Autodesk Fusion 360 part; units mm, degrees
(part 6 of 9)
equation "d71 = ( ( keyRowOne ) - upperSwitchOpening / 2 ) + faceOriginV"
equation "d72 = ( ( ( layoutGap + keycapSize / 2 + 0 * keyPitch ) - upperSwitchOpening / 2 ) + ( upperSwitchOpening ) ) - ( ( layoutGap + keycapSize / 2 + 0 * keyPitch ) - upperSwitchOpening / 2 )"
equation "d73 = ( ( ( ( keyRowOne ) - upperSwitchOpening / 2 ) + faceOriginV ) + ( upperSwitchOpening ) ) - ( ( ( keyRowOne ) - upperSwitchOpening / 2 ) + faceOriginV )"
equation "d74 = -( shellWall + 1 mm )"
equation "d76 = ( layoutGap + keycapSize / 2 + 1 * keyPitch ) - switchOpening / 2"
equation "d77 = ( ( keyRowOne ) - switchOpening / 2 ) + faceOriginV"
equation "d78 = ( ( ( layoutGap + keycapSize / 2 + 1 * keyPitch ) - switchOpening / 2 ) + ( switchOpening ) ) - ( ( layoutGap + keycapSize / 2 + 1 * keyPitch ) - switchOpening / 2 )"
equation "d79 = ( ( ( ( keyRowOne ) - switchOpening / 2 ) + faceOriginV ) + ( switchOpening ) ) - ( ( ( keyRowOne ) - switchOpening / 2 ) + faceOriginV )"
equation "d80 = -( carrierThickness + 1 mm )"
equation "d82 = ( layoutGap + keycapSize / 2 + 1 * keyPitch ) - upperSwitchOpening / 2"
equation "d83 = ( ( keyRowOne ) - upperSwitchOpening / 2 ) + faceOriginV"
equation "d84 = ( ( ( layoutGap + keycapSize / 2 + 1 * keyPitch ) - upperSwitchOpening / 2 ) + ( upperSwitchOpening ) ) - ( ( layoutGap + keycapSize / 2 + 1 * keyPitch ) - upperSwitchOpening / 2 )"
equation "d85 = ( ( ( ( keyRowOne ) - upperSwitchOpening / 2 ) + faceOriginV ) + ( upperSwitchOpening ) ) - ( ( ( keyRowOne ) - upperSwitchOpening / 2 ) + faceOriginV )"
equation "d86 = -( shellWall + 1 mm )"
equation "d88 = ( layoutGap + keycapSize / 2 + 2 * keyPitch ) - switchOpening / 2"
equation "d89 = ( ( keyRowOne ) - switchOpening / 2 ) + faceOriginV"
equation "d90 = ( ( ( layoutGap + keycapSize / 2 + 2 * keyPitch ) - switchOpening / 2 ) + ( switchOpening ) ) - ( ( layoutGap + keycapSize / 2 + 2 * keyPitch ) - switchOpening / 2 )"
equation "d91 = ( ( ( ( keyRowOne ) - switchOpening / 2 ) + faceOriginV ) + ( switchOpening ) ) - ( ( ( keyRowOne ) - switchOpening / 2 ) + faceOriginV )"
equation "d92 = -( carrierThickness + 1 mm )"
equation "d94 = ( layoutGap + keycapSize / 2 + 2 * keyPitch ) - upperSwitchOpening / 2"
equation "d95 = ( ( keyRowOne ) - upperSwitchOpening / 2 ) + faceOriginV"
equation "d96 = ( ( ( layoutGap + keycapSize / 2 + 2 * keyPitch ) - upperSwitchOpening / 2 ) + ( upperSwitchOpening ) ) - ( ( layoutGap + keycapSize / 2 + 2 * keyPitch ) - upperSwitchOpening / 2 )"
equation "d97 = ( ( ( ( keyRowOne ) - upperSwitchOpening / 2 ) + faceOriginV ) + ( upperSwitchOpening ) ) - ( ( ( keyRowOne ) - upperSwitchOpening / 2 ) + faceOriginV )"
equation "d98 = -( shellWall + 1 mm )"
equation "d100 = ( layoutGap + keycapSize / 2 + 0 * keyPitch ) - switchOpening / 2"
equation "d101 = ( ( keyRowTwo ) - switchOpening / 2 ) + faceOriginV"
equation "d102 = ( ( ( layoutGap + keycapSize / 2 + 0 * keyPitch ) - switchOpening / 2 ) + ( switchOpening ) ) - ( ( layoutGap + keycapSize / 2 + 0 * keyPitch ) - switchOpening / 2 )"
equation "d103 = ( ( ( ( keyRowTwo ) - switchOpening / 2 ) + faceOriginV ) + ( switchOpening ) ) - ( ( ( keyRowTwo ) - switchOpening / 2 ) + faceOriginV )"
equation "d104 = -( carrierThickness + 1 mm )"
equation "d106 = ( layoutGap + keycapSize / 2 + 0 * keyPitch ) - upperSwitchOpening / 2"
equation "d107 = ( ( keyRowTwo ) - upperSwitchOpening / 2 ) + faceOriginV"
equation "d108 = ( ( ( layoutGap + keycapSize / 2 + 0 * keyPitch ) - upperSwitchOpening / 2 ) + ( upperSwitchOpening ) ) - ( ( layoutGap + keycapSize / 2 + 0 * keyPitch ) - upperSwitchOpening / 2 )"
equation "d109 = ( ( ( ( keyRowTwo ) - upperSwitchOpening / 2 ) + faceOriginV ) + ( upperSwitchOpening ) ) - ( ( ( keyRowTwo ) - upperSwitchOpening / 2 ) + faceOriginV )"
equation "d110 = -( shellWall + 1 mm )"
equation "d112 = ( layoutGap + keycapSize / 2 + 1 * keyPitch ) - switchOpening / 2"
equation "d113 = ( ( keyRowTwo ) - switchOpening / 2 ) + faceOriginV"
equation "d114 = ( ( ( layoutGap + keycapSize / 2 + 1 * keyPitch ) - switchOpening / 2 ) + ( switchOpening ) ) - ( ( layoutGap + keycapSize / 2 + 1 * keyPitch ) - switchOpening / 2 )"
equation "d115 = ( ( ( ( keyRowTwo ) - switchOpening / 2 ) + faceOriginV ) + ( switchOpening ) ) - ( ( ( keyRowTwo ) - switchOpening / 2 ) + faceOriginV )"
equation "d116 = -( carrierThickness + 1 mm )"
equation "d118 = ( layoutGap + keycapSize / 2 + 1 * keyPitch ) - upperSwitchOpening / 2"
equation "d119 = ( ( keyRowTwo ) - upperSwitchOpening / 2 ) + faceOriginV"
equation "d120 = ( ( ( layoutGap + keycapSize / 2 + 1 * keyPitch ) - upperSwitchOpening / 2 ) + ( upperSwitchOpening ) ) - ( ( layoutGap + keycapSize / 2 + 1 * keyPitch ) - upperSwitchOpening / 2 )"
equation "d121 = ( ( ( ( keyRowTwo ) - upperSwitchOpening / 2 ) + faceOriginV ) + ( upperSwitchOpening ) ) - ( ( ( keyRowTwo ) - upperSwitchOpening / 2 ) + faceOriginV )"
equation "d122 = -( shellWall + 1 mm )"
equation "d124 = ( layoutGap + keycapSize / 2 + 2 * keyPitch ) - switchOpening / 2"
equation "d125 = ( ( keyRowTwo ) - switchOpening / 2 ) + faceOriginV"
equation "d126 = ( ( ( layoutGap + keycapSize / 2 + 2 * keyPitch ) - switchOpening / 2 ) + ( switchOpening ) ) - ( ( layoutGap + keycapSize / 2 + 2 * keyPitch ) - switchOpening / 2 )"
equation "d127 = ( ( ( ( keyRowTwo ) - switchOpening / 2 ) + faceOriginV ) + ( switchOpening ) ) - ( ( ( keyRowTwo ) - switchOpening / 2 ) + faceOriginV )"
equation "d128 = -( carrierThickness + 1 mm )"
equation "d130 = ( layoutGap + keycapSize / 2 + 2 * keyPitch ) - upperSwitchOpening / 2"
equation "d131 = ( ( keyRowTwo ) - upperSwitchOpening / 2 ) + faceOriginV"
equation "d132 = ( ( ( layoutGap + keycapSize / 2 + 2 * keyPitch ) - upperSwitchOpening / 2 ) + ( upperSwitchOpening ) ) - ( ( layoutGap + keycapSize / 2 + 2 * keyPitch ) - upperSwitchOpening / 2 )"
equation "d133 = ( ( ( ( keyRowTwo ) - upperSwitchOpening / 2 ) + faceOriginV ) + ( upperSwitchOpening ) ) - ( ( ( keyRowTwo ) - upperSwitchOpening / 2 ) + faceOriginV )"
equation "d134 = -( shellWall + 1 mm )"
equation "d136 = ( caseWidth - ledWidth ) / 2"
equation "d137 = ( ledCenter - ledHeight / 2 ) + faceOriginV"
equation "d138 = ( ( ( caseWidth - ledWidth ) / 2 ) + ( ledWidth ) ) - ( ( caseWidth - ledWidth ) / 2 )"
equation "d139 = ( ( ( ledCenter - ledHeight / 2 ) + faceOriginV ) + ( ledHeight ) ) - ( ( ledCenter - ledHeight / 2 ) + faceOriginV )"
equation "d140 = -( shellWall + 1 mm )"
equation "d142 = layoutGap"
equation "d143 = ( controlCenter - displayHeight / 2 ) + faceOriginV"
equation "d144 = ( ( layoutGap ) + ( displayWidth ) ) - ( layoutGap )"
equation "d145 = ( ( ( controlCenter - displayHeight / 2 ) + faceOriginV ) + ( displayHeight ) ) - ( ( controlCenter - displayHeight / 2 ) + faceOriginV )"
equation "d146 = -( shellWall + 1 mm )"
equation "d148 = encoderCenterX"
equation "d149 = controlCenter + faceOriginV"
equation "d150 = encoderHole"
equation "d151 = -( shellWall + 1 mm )"
equation "d153 = ( ( 0 mm ) + ( caseWidth ) ) - ( 0 mm )"
equation "d154 = ( ( 0 mm ) + ( caseLength ) ) - ( 0 mm )"
equation "d155 = bottomThickness"
equation "d157 = ( caseWidth - ledWidth ) / 2 + diffuserClearance"
equation "d158 = ( ledCenter - ledHeight / 2 + diffuserClearance ) + faceOriginV"
equation "d159 = ( ( ( caseWidth - ledWidth ) / 2 + diffuserClearance ) + ( ledWidth - 2 * diffuserClearance ) ) - ( ( caseWidth - ledWidth ) / 2 + diffuserClearance )"
equation "d160 = ( ( ( ledCenter - ledHeight / 2 + diffuserClearance ) + faceOriginV ) + ( ledHeight - 2 * diffuserClearance ) ) - ( ( ledCenter - ledHeight / 2 + diffuserClearance ) + faceOriginV )"
equation "d161 = -( shellWall )"
equation "d163 = -shellWall"
equation "d165 = ( caseWidth - ledWidth ) / 2 + diffuserClearance - diffuserFlange"
equation "d166 = ( ledCenter - ledHeight / 2 + diffuserClearance - diffuserFlange ) + faceOriginV"
equation "d167 = ( ( ( caseWidth - ledWidth ) / 2 + diffuserClearance - diffuserFlange ) + ( ledWidth - 2 * diffuserClearance + 2 * diffuserFlange ) ) - ( ( caseWidth - ledWidth ) / 2 + diffuserClearance - diffuserFlange )"
equation "d168 = ( ( ( ledCenter - ledHeight / 2 + diffuserClearance - diffuserFlange ) + faceOriginV ) + ( ledHeight - 2 * diffuserClearance + 2 * diffuserFlange ) ) - ( ( ledCenter - ledHeight / 2 + diffuserClearance - diffuserFlange ) + faceOriginV )"
equation "d169 = -( diffuserFlangeThickness )"
equation "carrierFaceLength = faceLength - 2 * ( shellWall + carrierClearance ) / cos(caseTilt) - carrierThickness * tan(caseTilt)" comment "Carrier rear clearance"
equation "d172 = layoutGap + 0 * keyPitch"
equation "d173 = ( keyRowOne - keycapSize / 2 ) + faceOriginV"
equation "d174 = ( ( layoutGap + 0 * keyPitch ) + ( keycapSize ) ) - ( layoutGap + 0 * keyPitch )"
equation "d175 = ( ( ( keyRowOne - keycapSize / 2 ) + faceOriginV ) + ( keycapSize ) ) - ( ( keyRowOne - keycapSize / 2 ) + faceOriginV )"
equation "d176 = layoutGap + 1 * keyPitch"
equation "d177 = ( keyRowOne - keycapSize / 2 ) + faceOriginV"
equation "d178 = ( ( layoutGap + 1 * keyPitch ) + ( keycapSize ) ) - ( layoutGap + 1 * keyPitch )"
equation "d179 = ( ( ( keyRowOne - keycapSize / 2 ) + faceOriginV ) + ( keycapSize ) ) - ( ( keyRowOne - keycapSize / 2 ) + faceOriginV )"
equation "d180 = layoutGap + 2 * keyPitch"
equation "d181 = ( keyRowOne - keycapSize / 2 ) + faceOriginV"
equation "d182 = ( ( layoutGap + 2 * keyPitch ) + ( keycapSize ) ) - ( layoutGap + 2 * keyPitch )"
equation "d183 = ( ( ( keyRowOne - keycapSize / 2 ) + faceOriginV ) + ( keycapSize ) ) - ( ( keyRowOne - keycapSize / 2 ) + faceOriginV )"
equation "d184 = layoutGap + 0 * keyPitch"
equation "d185 = ( keyRowTwo - keycapSize / 2 ) + faceOriginV"
equation "d186 = ( ( layoutGap + 0 * keyPitch ) + ( keycapSize ) ) - ( layoutGap + 0 * keyPitch )"
equation "d187 = ( ( ( keyRowTwo - keycapSize / 2 ) + faceOriginV ) + ( keycapSize ) ) - ( ( keyRowTwo - keycapSize / 2 ) + faceOriginV )"
equation "d188 = layoutGap + 1 * keyPitch"
equation "d189 = ( keyRowTwo - keycapSize / 2 ) + faceOriginV"
equation "d190 = ( ( layoutGap + 1 * keyPitch ) + ( keycapSize ) ) - ( layoutGap + 1 * keyPitch )"
equation "d191 = ( ( ( keyRowTwo - keycapSize / 2 ) + faceOriginV ) + ( keycapSize ) ) - ( ( keyRowTwo - keycapSize / 2 ) + faceOriginV )"
equation "d192 = layoutGap + 2 * keyPitch"
equation "d193 = ( keyRowTwo - keycapSize / 2 ) + faceOriginV"
equation "d194 = ( ( layoutGap + 2 * keyPitch ) + ( keycapSize ) ) - ( layoutGap + 2 * keyPitch )"
equation "d195 = ( ( ( keyRowTwo - keycapSize / 2 ) + faceOriginV ) + ( keycapSize ) ) - ( ( keyRowTwo - keycapSize / 2 ) + faceOriginV )"
equation "d196 = encoderCenterX"
equation "d197 = controlCenter + faceOriginV"
equation "d198 = encoderKnobDiameter"
equation "flangePocketClearance = 0.2 mm" comment "Carrier pocket clearance"
equation "d200 = ( caseWidth - ledWidth ) / 2 + diffuserClearance - diffuserFlange - flangePocketClearance"
equation "d201 = ( ledCenter - ledHeight / 2 + diffuserClearance - diffuserFlange - flangePocketClearance ) + faceOriginV"
equation "d202 = ( ( ( caseWidth - ledWidth ) / 2 + diffuserClearance - diffuserFlange - flangePocketClearance ) + ( ledWidth - 2 * diffuserClearance + 2 * diffuserFlange + 2 * flangePocketClearance ) ) - ( ( caseWidth - ledWidth ) / 2 + diffuserClearance - diffuserFlange - flangePocketClearance )"
equation "d203 = ( ( ( ledCenter - ledHeight / 2 + diffuserClearance - diffuserFlange - flangePocketClearance ) + faceOriginV ) + ( ledHeight - 2 * diffuserClearance + 2 * diffuserFlange + 2 * flangePocketClearance ) ) - ( ( ledCenter - ledHeight / 2 + diffuserClearance - diffuserFlange - flangePocketClearance ) + faceOriginV )"
equation "d204 = -( diffuserFlangeThickness - carrierClearance + flangePocketClearance )"
equation "carrierBayWidth = min(caseWidth - 2 * ( shellWall + carrierClearance + carrierRim ); ledWidth - 2 * diffuserClearance + 2 * diffuserFlange - 2 mm)" comment "Electronics opening preserving diffuser support rails"
equation "mountSideX = 12 mm" comment "Carrier fastener center from side"
equation "mountFrontV = 10.5 mm" comment "Front fastener center in face coordinates"
equation "mountRearV = faceLength - 9.64 mm" comment "Rear fastener center in face coordinates"
equation "mountBossDiameter = 7 mm" comment "Wall-connected M2 boss diameter"
equation "insertLength = 4 mm" comment "Confirmed M2 insert length"
equation "insertOuterDiameter = 3.5 mm" comment "Confirmed M2 insert outer diameter"
equation "insertPilotDiameter = 3.2 mm" comment "Provisional PLA pilot; test coupon required"
equation "insertPilotDepth = insertLength + 0.5 mm" comment "Blind insert pocket depth"
equation "carrierBossDepth = 7.4 mm" comment "Shell boss bottom below exterior face"
equation "carrierPadDepth = 10 mm" comment "Carrier pad bottom below exterior face"
equation "mountPocketClearance = 0.3 mm + ( carrierBossDepth - shellWall - carrierClearance ) * tan(caseTilt)" comment "Per-side carrier boss clearance"
equation "mountPadWidth = 12 mm" comment "Carrier mounting pad width"
equation "mountPadLength = 9.4 mm" comment "Carrier mounting pad length"
equation "m2Clearance = 2.3 mm" comment "Draft M2 screw clearance"
equation "bottomBossHeight = 6 mm" comment "Independent cover boss height above lid"
equation "carrierRibWidth = 2 mm" comment "Switch-field reinforcing rib width"
equation "carrierRibDepth = 3 mm" comment "Reinforcement below switch plate"
equation "d224 = -carrierBossDepth"
equation "d226 = -( carrierBossDepth + carrierClearance )"
equation "d228 = bottomThickness"
equation "d230 = mountSideX"
equation "d231 = ( mountFrontV ) + faceOriginV"
equation "d232 = mountBossDiameter"
equation "d233 = -( carrierBossDepth )"
equation "d235 = mountSideX"
equation "d236 = ( mountFrontV ) + faceOriginV"
equation "d237 = insertPilotDiameter"
equation "d238 = insertPilotDepth"
equation "d240 = ( mountSideX ) - mountPadWidth / 2"
equation "d241 = ( ( mountFrontV ) - mountPadLength / 2 ) + faceOriginV"
equation "d242 = ( ( shellWall + carrierClearance ) + ( mountPadWidth ) ) - ( shellWall + carrierClearance )"
equation "d243 = ( ( ( ( mountFrontV ) - mountPadLength / 2 ) + faceOriginV ) + ( mountPadLength ) ) - ( ( ( mountFrontV ) - mountPadLength / 2 ) + faceOriginV )"
equation "d244 = -( carrierPadDepth - shellWall - carrierClearance )"
equation "d246 = mountSideX"
equation "d247 = ( mountFrontV ) + faceOriginV"
equation "d248 = mountBossDiameter + 2 * mountPocketClearance"
equation "d249 = carrierBossDepth + carrierClearance"
equation "d251 = mountSideX"
equation "d252 = ( mountFrontV ) + faceOriginV"
equation "d253 = m2Clearance"
equation "d254 = -( carrierPadDepth )"
equation "d258 = bottomBossDiameter"
equation "d259 = bottomBossHeight"
equation "d263 = insertPilotDiameter"
equation "d264 = insertPilotDepth"
equation "d268 = m2Clearance"
equation "d269 = -( bottomThickness + 0.5 mm )"
equation "d271 = caseWidth - mountSideX"
equation "d272 = ( mountFrontV ) + faceOriginV"
equation "d273 = mountBossDiameter"
equation "d274 = -( carrierBossDepth )"
equation "d276 = caseWidth - mountSideX"
equation "d277 = ( mountFrontV ) + faceOriginV"
equation "d278 = insertPilotDiameter"
equation "d279 = insertPilotDepth"
equation "d281 = ( caseWidth - mountSideX ) - mountPadWidth / 2"
equation "d282 = ( ( mountFrontV ) - mountPadLength / 2 ) + faceOriginV"
equation "d283 = ( ( caseWidth - shellWall - carrierClearance - mountPadWidth ) + ( mountPadWidth ) ) - ( caseWidth - shellWall - carrierClearance - mountPadWidth )"
equation "d284 = ( ( ( ( mountFrontV ) - mountPadLength / 2 ) + faceOriginV ) + ( mountPadLength ) ) - ( ( ( mountFrontV ) - mountPadLength / 2 ) + faceOriginV )"
equation "d285 = -( carrierPadDepth - shellWall - carrierClearance )"
equation "d287 = caseWidth - mountSideX"
equation "d288 = ( mountFrontV ) + faceOriginV"
equation "d289 = mountBossDiameter + 2 * mountPocketClearance"
equation "d290 = carrierBossDepth + carrierClearance"
equation "d292 = caseWidth - mountSideX"
equation "d293 = ( mountFrontV ) + faceOriginV"
equation "d294 = m2Clearance"
equation "d295 = -( carrierPadDepth )"
equation "d297 = caseWidth - 20 mm"
equation "d299 = bottomBossDiameter"
equation "d300 = bottomBossHeight"
equation "d302 = caseWidth - 20 mm"
equation "d304 = insertPilotDiameter"
equation "d305 = insertPilotDepth"
equation "d307 = caseWidth - 20 mm"
equation "d309 = m2Clearance"
equation "d310 = -( bottomThickness + 0.5 mm )"
equation "d312 = mountSideX"
equation "d313 = ( mountRearV ) + faceOriginV"
equation "d314 = mountBossDiameter"
equation "d315 = -( carrierBossDepth )"
equation "d317 = mountSideX"
equation "d318 = ( mountRearV ) + faceOriginV"
equation "d319 = insertPilotDiameter"
equation "d320 = insertPilotDepth"
equation "d322 = ( mountSideX ) - mountPadWidth / 2"
equation "d323 = ( ( mountRearV ) - mountPadLength / 2 ) + faceOriginV"
equation "d324 = ( ( shellWall + carrierClearance ) + ( mountPadWidth ) ) - ( shellWall + carrierClearance )"
equation "d325 = ( ( ( ( mountRearV ) - mountPadLength / 2 ) + faceOriginV ) + ( mountPadLength ) ) - ( ( ( mountRearV ) - mountPadLength / 2 ) + faceOriginV )"
equation "d326 = -( carrierPadDepth - shellWall - carrierClearance )"
equation "d328 = mountSideX"
equation "d329 = ( mountRearV ) + faceOriginV"
equation "d330 = mountBossDiameter + 2 * mountPocketClearance"
equation "d331 = carrierBossDepth + carrierClearance"
equation "d333 = mountSideX"
equation "d334 = ( mountRearV ) + faceOriginV"
equation "d335 = m2Clearance"
equation "d336 = -( carrierPadDepth )"
equation "d338 = bottomRearSideX"
equation "d339 = caseLength - 3 mm"
equation "d340 = bottomBossDiameter"
equation "d341 = bottomBossHeight"
equation "d343 = bottomRearSideX"
equation "d344 = caseLength - 3 mm"
equation "d345 = insertPilotDiameter"
equation "d346 = insertPilotDepth"
equation "d348 = bottomRearSideX"
equation "d349 = caseLength - 3 mm"
equation "d350 = m2Clearance"
equation "d351 = -( bottomThickness + 0.5 mm )"
equation "d353 = caseWidth - mountSideX"
equation "d354 = ( mountRearV ) + faceOriginV"
equation "d355 = mountBossDiameter"
equation "d356 = -( carrierBossDepth )"
equation "d358 = caseWidth - mountSideX"
equation "d359 = ( mountRearV ) + faceOriginV"
equation "d360 = insertPilotDiameter"
equation "d361 = insertPilotDepth"
equation "d363 = ( caseWidth - mountSideX ) - mountPadWidth / 2"
equation "d364 = ( ( mountRearV ) - mountPadLength / 2 ) + faceOriginV"
equation "d365 = ( ( caseWidth - shellWall - carrierClearance - mountPadWidth ) + ( mountPadWidth ) ) - ( caseWidth - shellWall - carrierClearance - mountPadWidth )"
equation "d366 = ( ( ( ( mountRearV ) - mountPadLength / 2 ) + faceOriginV ) + ( mountPadLength ) ) - ( ( ( mountRearV ) - mountPadLength / 2 ) + faceOriginV )"
equation "d367 = -( carrierPadDepth - shellWall - carrierClearance )"
equation "d369 = caseWidth - mountSideX"
equation "d370 = ( mountRearV ) + faceOriginV"
equation "d371 = mountBossDiameter + 2 * mountPocketClearance"
equation "d372 = carrierBossDepth + carrierClearance"
equation "d374 = caseWidth - mountSideX"
equation "d375 = ( mountRearV ) + faceOriginV"
equation "d376 = m2Clearance"
equation "d377 = -( carrierPadDepth )"
equation "d379 = caseWidth - bottomRearSideX"
equation "d380 = caseLength - 3 mm"
equation "d381 = bottomBossDiameter"
equation "d382 = bottomBossHeight"
equation "d384 = caseWidth - bottomRearSideX"
equation "d385 = caseLength - 3 mm"
equation "d386 = insertPilotDiameter"
equation "d387 = insertPilotDepth"
equation "d389 = caseWidth - bottomRearSideX"
equation "d390 = caseLength - 3 mm"
equation "d391 = m2Clearance"
equation "d392 = -( bottomThickness + 0.5 mm )"
equation "d394 = ( layoutGap + keycapSize / 2 + ( 0 + 0.5 ) * keyPitch ) - carrierRibWidth / 2"
equation "d395 = ( mountFrontV + mountPadLength / 2 ) + faceOriginV"
equation "d396 = ( ( ( layoutGap + keycapSize / 2 + ( 0 + 0.5 ) * keyPitch ) - carrierRibWidth / 2 ) + ( carrierRibWidth ) ) - ( ( layoutGap + keycapSize / 2 + ( 0 + 0.5 ) * keyPitch ) - carrierRibWidth / 2 )"
equation "d397 = ( ( ( mountFrontV + mountPadLength / 2 ) + faceOriginV ) + ( keyRowTwo + keycapSize / 2 + 1 mm - mountFrontV - mountPadLength / 2 ) ) - ( ( mountFrontV + mountPadLength / 2 ) + faceOriginV )"
equation "d398 = -( carrierThickness + carrierRibDepth )"
equation "d400 = ( layoutGap + keycapSize / 2 + ( 1 + 0.5 ) * keyPitch ) - carrierRibWidth / 2"
equation "d401 = ( mountFrontV + mountPadLength / 2 ) + faceOriginV"
equation "d402 = ( ( ( layoutGap + keycapSize / 2 + ( 1 + 0.5 ) * keyPitch ) - carrierRibWidth / 2 ) + ( carrierRibWidth ) ) - ( ( layoutGap + keycapSize / 2 + ( 1 + 0.5 ) * keyPitch ) - carrierRibWidth / 2 )"
equation "d403 = ( ( ( mountFrontV + mountPadLength / 2 ) + faceOriginV ) + ( keyRowTwo + keycapSize / 2 + 1 mm - mountFrontV - mountPadLength / 2 ) ) - ( ( mountFrontV + mountPadLength / 2 ) + faceOriginV )"
equation "d404 = -( carrierThickness + carrierRibDepth )"
equation "d407 = ( ( keyRowOne + keyRowTwo ) / 2 - carrierRibWidth / 2 ) + faceOriginV"
equation "d408 = ( ( 10 mm ) + ( caseWidth - 20 mm ) ) - ( 10 mm )"
equation "d409 = ( ( ( ( keyRowOne + keyRowTwo ) / 2 - carrierRibWidth / 2 ) + faceOriginV ) + ( carrierRibWidth ) ) - ( ( ( keyRowOne + keyRowTwo ) / 2 - carrierRibWidth / 2 ) + faceOriginV )"
equation "d410 = -( carrierThickness + carrierRibDepth )"
equation "bottomBossDiameter = 6 mm" comment "Cover boss diameter; corner insertion relief"
equation "bottomReliefClearance = 0.2 mm" comment "Radial clearance for carrier removal past cover bosses"
equation "d416 = bottomBossDiameter + 2 * bottomReliefClearance"
equation "d417 = rearHeight + 1 mm"
equation "d419 = caseWidth - 20 mm"
equation "d421 = bottomBossDiameter + 2 * bottomReliefClearance"
equation "d422 = rearHeight + 1 mm"
equation "d424 = bottomRearSideX"
equation "d425 = caseLength - 3 mm"
equation "d426 = bottomBossDiameter + 2 * bottomReliefClearance"
equation "d427 = rearHeight + 1 mm"
equation "d429 = caseWidth - bottomRearSideX"
equation "d430 = caseLength - 3 mm"
equation "d431 = bottomBossDiameter + 2 * bottomReliefClearance"
equation "d432 = rearHeight + 1 mm"
equation "pcbWidth = 70 mm" comment "Confirmed board width"
equation "pcbLength = 50 mm" comment "Confirmed board length"
equation "pcbThickness = 1.6 mm" comment "Confirmed board thickness"
equation "pcbHolePitchX = 66 mm" comment "Confirmed hole center spacing across board"
equation "pcbHolePitchY = 46 mm" comment "Confirmed hole center spacing along board"
equation "pcbRearGap = 0.4 mm" comment "Provisional board-to-rear-wall clearance"
equation "pcbUndersideHeight = pcbMountHeight - pcbThickness" comment "Provisional PCB underside, clearing lower bosses"
equation "pcbTopHeight = pcbMountHeight" comment "PCB top reference"
equation "pcbLeft = ( caseWidth - pcbWidth ) / 2" comment "Centered board left edge"
equation "pcbRear = caseLength - shellWall - pcbRearGap" comment "Board rear edge"
equation "pcbFront = pcbRear - pcbLength" comment "Board front edge"
equation "usbCenterX = pcbLeft + pcbWidth - 36 mm" comment "Confirmed USB center from board left edge"
equation "usbCenterZ = pcbUndersideHeight - 5.5 mm" comment "USB center above PCB top"
equation "headerMaxHeight = 17 mm" comment "Local header envelope; footprints pending"
equation "d448 = pcbUndersideHeight"
equation "d450 = pcbTopHeight"
equation "d452 = pcbLeft"
equation "d453 = pcbFront"
equation "d454 = ( ( pcbLeft ) + ( pcbWidth ) ) - ( pcbLeft )"
equation "d455 = ( ( pcbFront ) + ( pcbLength ) ) - ( pcbFront )"
equation "d456 = pcbLeft"
equation "d457 = pcbFront"
equation "d458 = ( ( pcbLeft ) + ( pcbWidth ) ) - ( pcbLeft )"
equation "d459 = ( ( pcbFront ) + ( pcbLength ) ) - ( pcbFront )"
equation "d460 = pcbLeft + ( pcbWidth - pcbHolePitchX ) / 2 + 0 * pcbHolePitchX"
equation "d461 = pcbFront + ( pcbLength - pcbHolePitchY ) / 2 + 0 * pcbHolePitchY"
equation "d462 = pcbLeft + ( pcbWidth - pcbHolePitchX ) / 2 + 1 * pcbHolePitchX"
equation "d463 = pcbFront + ( pcbLength - pcbHolePitchY ) / 2 + 0 * pcbHolePitchY"
equation "d464 = pcbLeft + ( pcbWidth - pcbHolePitchX ) / 2 + 0 * pcbHolePitchX"
equation "d465 = pcbFront + ( pcbLength - pcbHolePitchY ) / 2 + 1 * pcbHolePitchY"
equation "d466 = pcbLeft + ( pcbWidth - pcbHolePitchX ) / 2 + 1 * pcbHolePitchX"
equation "d467 = pcbFront + ( pcbLength - pcbHolePitchY ) / 2 + 1 * pcbHolePitchY"
equation "headerRoutingTarget = 14 mm" comment "Conditional mated header and wire envelope; physical verification required"
equation "xh3Length = 10 mm" comment "Measured 3-pin connector length"
equation "xh4Length = 13 mm" comment "Measured 4-pin connector length"
equation "xh5Length = 15 mm" comment "Measured 5-pin connector length"
equation "sideHeaderInset = 3 mm" comment "User-supplied side header inset; reference edge to verify"
equation "bottomRearSideX = 20 mm" comment "Preserved lower rear fastener position"
equation "frontSupportWidth = bottomBossDiameter" comment "Front cover support width"
equation "frontSupportRun = 4.8 mm + bottomBossDiameter / 2 - shellWall + 0.1 mm" comment "45 degree support run and rise"
equation "d476 = ( caseWidth - ledWidth ) / 2 + diffuserClearance - diffuserFlange - flangePocketClearance"
equation "d477 = ( ledCenter - ledHeight / 2 + diffuserClearance - diffuserFlange - flangePocketClearance ) + faceOriginV"
equation "d478 = ( ( ( caseWidth - ledWidth ) / 2 + diffuserClearance - diffuserFlange - flangePocketClearance ) + ( ledWidth - 2 * diffuserClearance + 2 * diffuserFlange + 2 * flangePocketClearance ) ) - ( ( caseWidth - ledWidth ) / 2 + diffuserClearance - diffuserFlange - flangePocketClearance )"
equation "d479 = ( ( ( ledCenter - ledHeight / 2 + diffuserClearance - diffuserFlange - flangePocketClearance ) + faceOriginV ) + ( ledHeight - 2 * diffuserClearance + 2 * diffuserFlange + 2 * flangePocketClearance ) ) - ( ( ledCenter - ledHeight / 2 + diffuserClearance - diffuserFlange - flangePocketClearance ) + faceOriginV )"
equation "d480 = -( diffuserFlangeThickness - carrierClearance + flangePocketClearance )"
equation "d482 = ( 20 mm ) - frontSupportWidth / 2"
equation "d484 = -( ( 0 ) * ( shellWall - 0.1 mm ) + ( -1 ) * ( bottomThickness + bottomBossHeight ) )"
equation "d485 = ( 1 ) * ( shellWall - 0.1 mm ) + ( 0 ) * ( bottomThickness + bottomBossHeight )"
equation "d486 = ( ( 1 ) * ( shellWall - 0.1 mm + frontSupportRun ) + ( 0 ) * ( bottomThickness + bottomBossHeight ) ) - ( ( 1 ) * ( shellWall - 0.1 mm ) + ( 0 ) * ( bottomThickness + bottomBossHeight ) )"
equation "d487 = ( ( 0 ) * ( shellWall - 0.1 mm ) + ( -1 ) * ( bottomThickness + bottomBossHeight ) ) - ( ( 0 ) * ( shellWall - 0.1 mm ) + ( -1 ) * ( bottomThickness + bottomBossHeight + frontSupportRun ) )"
equation "d488 = frontSupportWidth"
equation "d490 = ( 20 mm ) - bottomBossDiameter / 2 - bottomReliefClearance"
equation "d491 = ( ( ( 20 mm ) - bottomBossDiameter / 2 - bottomReliefClearance ) + ( bottomBossDiameter + 2 * bottomReliefClearance ) ) - ( ( 20 mm ) - bottomBossDiameter / 2 - bottomReliefClearance )"
equation "d492 = ( ( 0 mm ) + ( 4.8 mm + bottomBossDiameter / 2 + bottomReliefClearance ) ) - ( 0 mm )"
equation "d493 = rearHeight + 1 mm"
equation "d495 = ( caseWidth - 20 mm ) - frontSupportWidth / 2"
equation "d497 = -( ( 0 ) * ( shellWall - 0.1 mm ) + ( -1 ) * ( bottomThickness + bottomBossHeight ) )"
equation "d498 = ( 1 ) * ( shellWall - 0.1 mm ) + ( 0 ) * ( bottomThickness + bottomBossHeight )"
equation "d499 = ( ( 1 ) * ( shellWall - 0.1 mm + frontSupportRun ) + ( 0 ) * ( bottomThickness + bottomBossHeight ) ) - ( ( 1 ) * ( shellWall - 0.1 mm ) + ( 0 ) * ( bottomThickness + bottomBossHeight ) )"
equation "d500 = ( ( 0 ) * ( shellWall - 0.1 mm ) + ( -1 ) * ( bottomThickness + bottomBossHeight ) ) - ( ( 0 ) * ( shellWall - 0.1 mm ) + ( -1 ) * ( bottomThickness + bottomBossHeight + frontSupportRun ) )"
equation "d501 = frontSupportWidth"
equation "d503 = ( caseWidth - 20 mm ) - bottomBossDiameter / 2 - bottomReliefClearance"
equation "d504 = ( ( ( caseWidth - 20 mm ) - bottomBossDiameter / 2 - bottomReliefClearance ) + ( bottomBossDiameter + 2 * bottomReliefClearance ) ) - ( ( caseWidth - 20 mm ) - bottomBossDiameter / 2 - bottomReliefClearance )"
equation "d505 = ( ( 0 mm ) + ( 4.8 mm + bottomBossDiameter / 2 + bottomReliefClearance ) ) - ( 0 mm )"
equation "d506 = rearHeight + 1 mm"
equation "diffuserSkin = 0.8 mm" comment "Prototype optical front skin"
equation "diffuserSideWall = 1 mm" comment "Prototype hollow plug walls"
equation "diffuserRearDepth = 6 mm" comment "Rear rim presses strip edges"
equation "ledTrayDepth = 6.2 mm" comment "LED strip seat below exterior face"
equation "ledTrayThickness = 2.4 mm" comment "Structural LED tray"
equation "ledWireWidth = 4 mm" comment "Right-hand prototype wiring relief"
equation "oledBoardWidth = 36 mm" comment "Measured PCB orientation across case"
equation "oledBoardLength = 34 mm" comment "Measured PCB orientation along face"
equation "oledPcbThickness = 1.6 mm" comment "Confirmed OLED PCB thickness"
equation "oledPcbFrontDepth = 2.8 mm" comment "Provisional OLED PCB front seating depth"
equation "oledFitClearance = 0.2 mm" comment "Prototype PCB fit clearance"
equation "oledBackDepth = oledPcbFrontDepth + oledPcbThickness" comment "OLED PCB rear face"
equation "pcbPostDiameter = 4.4 mm" comment "Trial PCB screw support diameter"
equation "pcbPostHeight = pcbRailHeight + pcbRailThickness - pcbMountHeight" comment "Short PCB posts below control hardware"
equation "pcbPostPilot = 1.7 mm" comment "Trial M2 plastic thread pilot; coupon required"
equation "d523 = -( shellWall + diffuserFlangeThickness )"
equation "d525 = ( caseWidth - ledWidth ) / 2 + diffuserClearance - diffuserFlange"
equation "d526 = ( ledCenter - ledHeight / 2 + diffuserClearance - diffuserFlange ) + faceOriginV"
equation "d527 = ( ( ( caseWidth - ledWidth ) / 2 + diffuserClearance - diffuserFlange ) + ( ledWidth - 2 * diffuserClearance + 2 * diffuserFlange ) ) - ( ( caseWidth - ledWidth ) / 2 + diffuserClearance - diffuserFlange )"
equation "d528 = ( ( ( ledCenter - ledHeight / 2 + diffuserClearance - diffuserFlange ) + faceOriginV ) + ( ledHeight - 2 * diffuserClearance + 2 * diffuserFlange ) ) - ( ( ledCenter - ledHeight / 2 + diffuserClearance - diffuserFlange ) + faceOriginV )"
equation "d529 = -( diffuserRearDepth - shellWall - diffuserFlangeThickness )"
equation "d531 = -diffuserSkin"
equation "d533 = ( caseWidth - ledWidth ) / 2 + diffuserClearance + diffuserSideWall"
equation "d534 = ( ledCenter - ledHeight / 2 + diffuserClearance + diffuserSideWall ) + faceOriginV"
equation "d535 = ( ( ( caseWidth - ledWidth ) / 2 + diffuserClearance + diffuserSideWall ) + ( ledWidth - 2 * ( diffuserClearance + diffuserSideWall ) ) ) - ( ( caseWidth - ledWidth ) / 2 + diffuserClearance + diffuserSideWall )"
equation "d536 = ( ( ( ledCenter - ledHeight / 2 + diffuserClearance + diffuserSideWall ) + faceOriginV ) + ( ledHeight - 2 * ( diffuserClearance + diffuserSideWall ) ) ) - ( ( ledCenter - ledHeight / 2 + diffuserClearance + diffuserSideWall ) + faceOriginV )"
equation "d537 = -( diffuserRearDepth + 1 mm )"
equation "d539 = ( caseWidth + ledWidth ) / 2 - diffuserSideWall - 1 mm"
equation "d540 = ( ledCenter - ledWireWidth / 2 ) + faceOriginV"
equation "d541 = ( ( ( caseWidth + ledWidth ) / 2 - diffuserSideWall - 1 mm ) + ( 5 mm ) ) - ( ( caseWidth + ledWidth ) / 2 - diffuserSideWall - 1 mm )"
equation "d542 = ( ( ( ledCenter - ledWireWidth / 2 ) + faceOriginV ) + ( ledWireWidth ) ) - ( ( ledCenter - ledWireWidth / 2 ) + faceOriginV )"
equation "d543 = -( diffuserRearDepth )"
equation "d545 = ( caseWidth - ledWidth ) / 2 + diffuserClearance - diffuserFlange - flangePocketClearance"
equation "d546 = ( ledCenter - ledHeight / 2 + diffuserClearance - diffuserFlange - flangePocketClearance ) + faceOriginV"
equation "d547 = ( ( ( caseWidth - ledWidth ) / 2 + diffuserClearance - diffuserFlange - flangePocketClearance ) + ( ledWidth - 2 * diffuserClearance + 2 * ( diffuserFlange + flangePocketClearance ) ) ) - ( ( caseWidth - ledWidth ) / 2 + diffuserClearance - diffuserFlange - flangePocketClearance )"
equation "d548 = ( ( ( ledCenter - ledHeight / 2 + diffuserClearance - diffuserFlange - flangePocketClearance ) + faceOriginV ) + ( ledHeight - 2 * diffuserClearance + 2 * ( diffuserFlange + flangePocketClearance ) ) ) - ( ( ledCenter - ledHeight / 2 + diffuserClearance - diffuserFlange - flangePocketClearance ) + faceOriginV )"
equation "d549 = -( diffuserRearDepth - shellWall - carrierClearance + 0.2 mm )"
equation "d551 = ( caseWidth - ledWidth ) / 2 - 0.2 mm"
equation "d552 = ( faceLength - ( shellWall + carrierClearance ) / cos(caseTilt) - ( shellWall + carrierClearance + carrierThickness ) * tan(caseTilt) - carrierRim + 0.4 mm ) + faceOriginV"
equation "d553 = ( ( ( caseWidth - ledWidth ) / 2 - 0.2 mm ) + ( ledWidth + 0.4 mm ) ) - ( ( caseWidth - ledWidth ) / 2 - 0.2 mm )"
equation "d554 = ( ( ( faceLength - ( shellWall + carrierClearance ) / cos(caseTilt) - ( shellWall + carrierClearance + carrierThickness ) * tan(caseTilt) - carrierRim + 0.4 mm ) + faceOriginV ) + ( 4 mm ) ) - ( ( faceLength - ( shellWall + carrierClearance ) / cos(caseTilt) - ( shellWall + carrierClearance + carrierThickness ) * tan(caseTilt) - carrierRim + 0.4 mm ) + faceOriginV )"
equation "d555 = -( ledTrayDepth + ledTrayThickness - shellWall - carrierClearance )"
equation "d557 = -ledTrayDepth"
equation "d559 = ( caseWidth - ledWidth ) / 2 - 0.2 mm"
equation "d560 = ( ledCenter - ledHeight / 2 - 0.2 mm ) + faceOriginV"
equation "d561 = ( ( ( caseWidth - ledWidth ) / 2 - 0.2 mm ) + ( ledWidth + 0.4 mm ) ) - ( ( caseWidth - ledWidth ) / 2 - 0.2 mm )"
equation "d562 = ( ( ( ledCenter - ledHeight / 2 - 0.2 mm ) + faceOriginV ) + ( ( faceLength - ( shellWall + carrierClearance ) / cos(caseTilt) - ( ledTrayDepth + ledTrayThickness ) * tan(caseTilt) ) - ( ledCenter - ledHeight / 2 - 0.2 mm ) ) ) - ( ( ledCenter - ledHeight / 2 - 0.2 mm ) + faceOriginV )"
equation "d563 = -( ledTrayThickness )"
equation "d565 = ( caseWidth + ledWidth ) / 2 - 2 mm"
equation "d566 = ( ledCenter - ledWireWidth / 2 ) + faceOriginV"
equation "d567 = ( ( ( caseWidth + ledWidth ) / 2 - 2 mm ) + ( 4 mm ) ) - ( ( caseWidth + ledWidth ) / 2 - 2 mm )"
equation "d568 = ( ( ( ledCenter - ledWireWidth / 2 ) + faceOriginV ) + ( ledWireWidth ) ) - ( ( ledCenter - ledWireWidth / 2 ) + faceOriginV )"
equation "d569 = -( ledTrayThickness + 1 mm )"
equation "d571 = layoutGap + ( displayWidth - oledBoardWidth ) / 2"
equation "d572 = ( controlCenter - oledBoardLength / 2 ) + faceOriginV"
equation "d573 = ( ( layoutGap + ( displayWidth - oledBoardWidth ) / 2 ) + ( oledBoardWidth ) ) - ( layoutGap + ( displayWidth - oledBoardWidth ) / 2 )"
equation "d574 = ( ( ( controlCenter - oledBoardLength / 2 ) + faceOriginV ) + ( 3 mm ) ) - ( ( controlCenter - oledBoardLength / 2 ) + faceOriginV )"
equation "d575 = -( oledPcbFrontDepth )"
equation "d577 = layoutGap + ( displayWidth - oledBoardWidth ) / 2"
equation "d578 = ( controlCenter + oledBoardLength / 2 - 5 mm ) + faceOriginV"
equation "d579 = ( ( layoutGap + ( displayWidth - oledBoardWidth ) / 2 ) + ( oledBoardWidth ) ) - ( layoutGap + ( displayWidth - oledBoardWidth ) / 2 )"
equation "d580 = ( ( ( controlCenter + oledBoardLength / 2 - 5 mm ) + faceOriginV ) + ( 3 mm ) ) - ( ( controlCenter + oledBoardLength / 2 - 5 mm ) + faceOriginV )"
equation "d581 = -( oledPcbFrontDepth )"
equation "d583 = layoutGap + ( displayWidth - oledBoardWidth ) / 2 - oledFitClearance"
equation "d584 = ( controlCenter - oledBoardLength / 2 - oledFitClearance ) + faceOriginV"
equation "d585 = ( ( layoutGap + ( displayWidth - oledBoardWidth ) / 2 - oledFitClearance ) + ( oledBoardWidth + 2 * oledFitClearance ) ) - ( layoutGap + ( displayWidth - oledBoardWidth ) / 2 - oledFitClearance )"
equation "d586 = ( ( ( controlCenter - oledBoardLength / 2 - oledFitClearance ) + faceOriginV ) + ( oledBoardLength + 2 * oledFitClearance ) ) - ( ( controlCenter - oledBoardLength / 2 - oledFitClearance ) + faceOriginV )"
equation "d587 = -( oledBackDepth + oledFitClearance - shellWall - carrierClearance )"
equation "d589 = -( oledBackDepth + oledFitClearance )"
equation "d592 = ( controlCenter - 18 mm ) + faceOriginV"
equation "d593 = ( ( 18 mm ) + ( 14 mm ) ) - ( 18 mm )"
equation "d594 = ( ( ( controlCenter - 18 mm ) + faceOriginV ) + ( 1 mm ) ) - ( ( controlCenter - 18 mm ) + faceOriginV )"
equation "d595 = -( oledBackDepth + oledFitClearance + 2 mm - shellWall - carrierClearance )"
equation "d598 = ( controlCenter - 18 mm ) + faceOriginV"
equation "d599 = ( ( 18 mm ) + ( 14 mm ) ) - ( 18 mm )"
equation "d600 = ( ( ( controlCenter - 18 mm ) + faceOriginV ) + ( 4 mm ) ) - ( ( controlCenter - 18 mm ) + faceOriginV )"
equation "d601 = -( 2 mm )"
equation "d604 = ( controlCenter + 12.8 mm ) + faceOriginV"
equation "d605 = ( ( 18 mm ) + ( 14 mm ) ) - ( 18 mm )"
equation "d606 = ( ( ( controlCenter + 12.8 mm ) + faceOriginV ) + ( 3.8 mm ) ) - ( ( controlCenter + 12.8 mm ) + faceOriginV )"
equation "d607 = -( ledTrayThickness )"
equation "d610 = ( controlCenter + 13 mm ) + faceOriginV"
equation "d611 = ( ( 18 mm ) + ( 14 mm ) ) - ( 18 mm )"
equation "d612 = ( ( ( controlCenter + 13 mm ) + faceOriginV ) + ( 2 mm ) ) - ( ( controlCenter + 13 mm ) + faceOriginV )"
equation "d613 = -( 2 mm )"
equation "d615 = layoutGap + ( displayWidth - oledBoardWidth ) / 2 - oledFitClearance"
equation "d616 = ( controlCenter - oledBoardLength / 2 - oledFitClearance ) + faceOriginV"
equation "d617 = ( ( layoutGap + ( displayWidth - oledBoardWidth ) / 2 - oledFitClearance ) + ( oledBoardWidth + 2 * oledFitClearance ) ) - ( layoutGap + ( displayWidth - oledBoardWidth ) / 2 - oledFitClearance )"
equation "d618 = ( ( ( controlCenter - oledBoardLength / 2 - oledFitClearance ) + faceOriginV ) + ( oledBoardLength + 2 * oledFitClearance ) ) - ( ( controlCenter - oledBoardLength / 2 - oledFitClearance ) + faceOriginV )"
equation "d619 = -( oledBackDepth + oledFitClearance - shellWall - carrierClearance )"
equation "d621 = pcbTopHeight + 4 mm"
equation "d624 = ( pcbFront + ( pcbLength - pcbHolePitchY ) / 2 + 0 * pcbHolePitchY ) - 2 mm"
equation "d625 = ( ( 3.2 mm ) + ( 1.6 mm ) ) - ( 3.2 mm )"
equation "d626 = ( ( ( pcbFront + ( pcbLength - pcbHolePitchY ) / 2 + 0 * pcbHolePitchY ) - 2 mm ) + ( 4 mm ) ) - ( ( pcbFront + ( pcbLength - pcbHolePitchY ) / 2 + 0 * pcbHolePitchY ) - 2 mm )"
equation "d630 = ( pcbFront + ( pcbLength - pcbHolePitchY ) / 2 + 0 * pcbHolePitchY ) - 2 mm"
equation "d631 = ( ( 3.2 mm ) + ( 3.8 mm ) ) - ( 3.2 mm )"
equation "d632 = ( ( ( pcbFront + ( pcbLength - pcbHolePitchY ) / 2 + 0 * pcbHolePitchY ) - 2 mm ) + ( 4 mm ) ) - ( ( pcbFront + ( pcbLength - pcbHolePitchY ) / 2 + 0 * pcbHolePitchY ) - 2 mm )"
equation "d635 = pcbLeft + ( pcbWidth - pcbHolePitchX ) / 2 + 0 * pcbHolePitchX"
equation "d636 = pcbFront + ( pcbLength - pcbHolePitchY ) / 2 + 0 * pcbHolePitchY"
equation "d637 = pcbPostDiameter"
equation "d640 = pcbLeft + ( pcbWidth - pcbHolePitchX ) / 2 + 0 * pcbHolePitchX"
equation "d641 = pcbFront + ( pcbLength - pcbHolePitchY ) / 2 + 0 * pcbHolePitchY"
equation "d642 = pcbPostPilot"
equation "d645 = caseWidth - 4.8 mm"
equation "d646 = ( pcbFront + ( pcbLength - pcbHolePitchY ) / 2 + 0 * pcbHolePitchY ) - 2 mm"
equation "d647 = ( ( caseWidth - 4.8 mm ) + ( 1.6 mm ) ) - ( caseWidth - 4.8 mm )"
equation "d648 = ( ( ( pcbFront + ( pcbLength - pcbHolePitchY ) / 2 + 0 * pcbHolePitchY ) - 2 mm ) + ( 4 mm ) ) - ( ( pcbFront + ( pcbLength - pcbHolePitchY ) / 2 + 0 * pcbHolePitchY ) - 2 mm )"
equation "d651 = caseWidth - 7 mm"
equation "d652 = ( pcbFront + ( pcbLength - pcbHolePitchY ) / 2 + 0 * pcbHolePitchY ) - 2 mm"
equation "d653 = ( ( caseWidth - 7 mm ) + ( 3.8 mm ) ) - ( caseWidth - 7 mm )"
equation "d654 = ( ( ( pcbFront + ( pcbLength - pcbHolePitchY ) / 2 + 0 * pcbHolePitchY ) - 2 mm ) + ( 4 mm ) ) - ( ( pcbFront + ( pcbLength - pcbHolePitchY ) / 2 + 0 * pcbHolePitchY ) - 2 mm )"
equation "d657 = pcbLeft + ( pcbWidth - pcbHolePitchX ) / 2 + 1 * pcbHolePitchX"
equation "d658 = pcbFront + ( pcbLength - pcbHolePitchY ) / 2 + 0 * pcbHolePitchY"
equation "d659 = pcbPostDiameter"
equation "d662 = pcbLeft + ( pcbWidth - pcbHolePitchX ) / 2 + 1 * pcbHolePitchX"
equation "d663 = pcbFront + ( pcbLength - pcbHolePitchY ) / 2 + 0 * pcbHolePitchY"
equation "d664 = pcbPostPilot"
equation "d668 = ( pcbFront + ( pcbLength - pcbHolePitchY ) / 2 + 1 * pcbHolePitchY ) - 2 mm"
equation "d669 = ( ( 3.2 mm ) + ( 1.6 mm ) ) - ( 3.2 mm )"
equation "d670 = ( ( ( pcbFront + ( pcbLength - pcbHolePitchY ) / 2 + 1 * pcbHolePitchY ) - 2 mm ) + ( 4 mm ) ) - ( ( pcbFront + ( pcbLength - pcbHolePitchY ) / 2 + 1 * pcbHolePitchY ) - 2 mm )"
equation "d674 = ( pcbFront + ( pcbLength - pcbHolePitchY ) / 2 + 1 * pcbHolePitchY ) - 2 mm"
equation "d675 = ( ( 3.2 mm ) + ( 3.8 mm ) ) - ( 3.2 mm )"
equation "d676 = ( ( ( pcbFront + ( pcbLength - pcbHolePitchY ) / 2 + 1 * pcbHolePitchY ) - 2 mm ) + ( 4 mm ) ) - ( ( pcbFront + ( pcbLength - pcbHolePitchY ) / 2 + 1 * pcbHolePitchY ) - 2 mm )"
equation "d679 = pcbLeft + ( pcbWidth - pcbHolePitchX ) / 2 + 0 * pcbHolePitchX"
equation "d680 = pcbFront + ( pcbLength - pcbHolePitchY ) / 2 + 1 * pcbHolePitchY"
equation "d681 = pcbPostDiameter"
equation "d684 = pcbLeft + ( pcbWidth - pcbHolePitchX ) / 2 + 0 * pcbHolePitchX"
equation "d685 = pcbFront + ( pcbLength - pcbHolePitchY ) / 2 + 1 * pcbHolePitchY"
equation "d686 = pcbPostPilot"
equation "d689 = caseWidth - 4.8 mm"
equation "d690 = ( pcbFront + ( pcbLength - pcbHolePitchY ) / 2 + 1 * pcbHolePitchY ) - 2 mm"
equation "d691 = ( ( caseWidth - 4.8 mm ) + ( 1.6 mm ) ) - ( caseWidth - 4.8 mm )"
equation "d692 = ( ( ( pcbFront + ( pcbLength - pcbHolePitchY ) / 2 + 1 * pcbHolePitchY ) - 2 mm ) + ( 4 mm ) ) - ( ( pcbFront + ( pcbLength - pcbHolePitchY ) / 2 + 1 * pcbHolePitchY ) - 2 mm )"
equation "d695 = caseWidth - 7 mm"
equation "d696 = ( pcbFront + ( pcbLength - pcbHolePitchY ) / 2 + 1 * pcbHolePitchY ) - 2 mm"
equation "d697 = ( ( caseWidth - 7 mm ) + ( 3.8 mm ) ) - ( caseWidth - 7 mm )"
equation "d698 = ( ( ( pcbFront + ( pcbLength - pcbHolePitchY ) / 2 + 1 * pcbHolePitchY ) - 2 mm ) + ( 4 mm ) ) - ( ( pcbFront + ( pcbLength - pcbHolePitchY ) / 2 + 1 * pcbHolePitchY ) - 2 mm )"
equation "d701 = pcbLeft + ( pcbWidth - pcbHolePitchX ) / 2 + 1 * pcbHolePitchX"
equation "d702 = pcbFront + ( pcbLength - pcbHolePitchY ) / 2 + 1 * pcbHolePitchY"
equation "d703 = pcbPostDiameter"
equation "d706 = pcbLeft + ( pcbWidth - pcbHolePitchX ) / 2 + 1 * pcbHolePitchX"
equation "d707 = pcbFront + ( pcbLength - pcbHolePitchY ) / 2 + 1 * pcbHolePitchY"
equation "d708 = pcbPostPilot"
equation "d711 = -( carrierBossDepth + carrierClearance )"
equation "d713 = mountSideX"
equation "d714 = ( mountFrontV ) + faceOriginV"
equation "d715 = mountBossDiameter"
equation "d716 = -( carrierClearance )"
equation "d718 = mountSideX"
equation "d719 = ( mountFrontV ) + faceOriginV"
equation "d720 = insertPilotDiameter"
equation "d721 = carrierClearance + 0.1 mm"
equation "d723 = caseWidth - mountSideX"
equation "d724 = ( mountFrontV ) + faceOriginV"
equation "d725 = mountBossDiameter"
equation "d726 = -( carrierClearance )"
equation "d728 = caseWidth - mountSideX"
equation "d729 = ( mountFrontV ) + faceOriginV"
equation "d730 = insertPilotDiameter"
equation "d731 = carrierClearance + 0.1 mm"
equation "d733 = mountSideX"
equation "d734 = ( mountRearV ) + faceOriginV"
equation "d735 = mountBossDiameter"
equation "d736 = -( carrierClearance )"
equation "d738 = mountSideX"
equation "d739 = ( mountRearV ) + faceOriginV"
equation "d740 = insertPilotDiameter"
equation "d741 = carrierClearance + 0.1 mm"
equation "d743 = mountSideX"
equation "d744 = ( mountRearV ) + faceOriginV"
equation "d745 = mountBossDiameter + 2 * mountPocketClearance"
equation "d746 = carrierBossDepth + carrierClearance"
equation "d748 = mountSideX"
equation "d749 = ( mountRearV ) + faceOriginV"
equation "d750 = m2Clearance"
equation "d751 = -( carrierPadDepth )"
equation "d754 = caseLength - 3 mm"
equation "d755 = bottomBossDiameter + 2 * bottomReliefClearance"
equation "d756 = rearHeight + 1 mm"
equation "d758 = caseWidth - mountSideX"
equation "d759 = ( mountRearV ) + faceOriginV"
equation "d760 = mountBossDiameter"
equation "d761 = -( carrierClearance )"
equation "d763 = caseWidth - mountSideX"
equation "d764 = ( mountRearV ) + faceOriginV"
equation "d765 = insertPilotDiameter"
equation "d766 = carrierClearance + 0.1 mm"
equation "d768 = caseWidth - mountSideX"
equation "d769 = ( mountRearV ) + faceOriginV"
equation "d770 = mountBossDiameter + 2 * mountPocketClearance"
equation "d771 = carrierBossDepth + carrierClearance"
equation "d773 = caseWidth - mountSideX"
equation "d774 = ( mountRearV ) + faceOriginV"
equation "d775 = m2Clearance"
equation "d776 = -( carrierPadDepth )"
equation "d778 = caseWidth - 20 mm"
equation "d779 = caseLength - 3 mm"
equation "d780 = bottomBossDiameter + 2 * bottomReliefClearance"
equation "d781 = rearHeight + 1 mm"
equation "pcbMountHeight = 22.3 mm" comment "Upper solder-side PCB seating face; components face bottom cover"
equation "pcbRailHeight = 27.8 mm" comment "Short screw bosses attach to continuous outer carrier rails"
equation "pcbRailThickness = 1.5 mm" comment "Mounting ear thickness"
equation "d788 = -( ( 0 ) * ( pcbFront ) + ( -1 ) * ( pcbRailHeight ) )"
equation "d789 = ( 1 ) * ( pcbFront ) + ( 0 ) * ( pcbRailHeight )"
equation "d790 = ( ( 1 ) * ( pcbRear ) + ( 0 ) * ( pcbRailHeight ) ) - ( ( 1 ) * ( pcbFront ) + ( 0 ) * ( pcbRailHeight ) )"
equation "d791 = -( ( ( 0 ) * ( pcbRear ) + ( -1 ) * ( frontHeight + pcbRear * tan(caseTilt) - ( shellWall + carrierClearance + carrierThickness - 0.3 mm ) / cos(caseTilt) ) ) - ( ( 0 ) * ( pcbRear ) + ( -1 ) * ( pcbRailHeight ) ) )"
equation "d792 = ( ( 0 ) * ( pcbFront ) + ( -1 ) * ( pcbRailHeight ) ) - ( ( 0 ) * ( pcbFront ) + ( -1 ) * ( frontHeight + pcbFront * tan(caseTilt) - ( shellWall + carrierClearance + carrierThickness - 0.3 mm ) / cos(caseTilt) ) )"
equation "d795 = caseWidth - 4.8 mm"
equation "d797 = -( ( 0 ) * ( pcbFront ) + ( -1 ) * ( pcbRailHeight ) )"
equation "d798 = ( 1 ) * ( pcbFront ) + ( 0 ) * ( pcbRailHeight )"
equation "d799 = ( ( 1 ) * ( pcbRear ) + ( 0 ) * ( pcbRailHeight ) ) - ( ( 1 ) * ( pcbFront ) + ( 0 ) * ( pcbRailHeight ) )"
equation "d800 = -( ( ( 0 ) * ( pcbRear ) + ( -1 ) * ( frontHeight + pcbRear * tan(caseTilt) - ( shellWall + carrierClearance + carrierThickness - 0.3 mm ) / cos(caseTilt) ) ) - ( ( 0 ) * ( pcbRear ) + ( -1 ) * ( pcbRailHeight ) ) )"
equation "d801 = ( ( 0 ) * ( pcbFront ) + ( -1 ) * ( pcbRailHeight ) ) - ( ( 0 ) * ( pcbFront ) + ( -1 ) * ( frontHeight + pcbFront * tan(caseTilt) - ( shellWall + carrierClearance + carrierThickness - 0.3 mm ) / cos(caseTilt) ) )"
equation "d804 = pcbRailHeight"
equation "d807 = ( pcbFront + ( pcbLength - pcbHolePitchY ) / 2 + 0 * pcbHolePitchY ) - 2.2 mm"
equation "d808 = ( ( 3.2 mm ) + ( 6 mm ) ) - ( 3.2 mm )"
equation "d809 = ( ( ( pcbFront + ( pcbLength - pcbHolePitchY ) / 2 + 0 * pcbHolePitchY ) - 2.2 mm ) + ( 4.4 mm ) ) - ( ( pcbFront + ( pcbLength - pcbHolePitchY ) / 2 + 0 * pcbHolePitchY ) - 2.2 mm )"
equation "d810 = pcbRailThickness"
equation "d812 = pcbLeft + ( pcbWidth - pcbHolePitchX ) / 2 + 0 * pcbHolePitchX"
equation "d813 = pcbFront + ( pcbLength - pcbHolePitchY ) / 2 + 0 * pcbHolePitchY"
equation "d814 = pcbPostDiameter"
equation "d815 = pcbPostHeight"
equation "d817 = pcbLeft + ( pcbWidth - pcbHolePitchX ) / 2 + 0 * pcbHolePitchX"
equation "d818 = pcbFront + ( pcbLength - pcbHolePitchY ) / 2 + 0 * pcbHolePitchY"
equation "d819 = pcbPostPilot"
equation "d822 = caseWidth - 9.2 mm"
equation "d823 = ( pcbFront + ( pcbLength - pcbHolePitchY ) / 2 + 0 * pcbHolePitchY ) - 2.2 mm"
equation "d824 = ( ( caseWidth - 9.2 mm ) + ( 6 mm ) ) - ( caseWidth - 9.2 mm )"
equation "d825 = ( ( ( pcbFront + ( pcbLength - pcbHolePitchY ) / 2 + 0 * pcbHolePitchY ) - 2.2 mm ) + ( 4.4 mm ) ) - ( ( pcbFront + ( pcbLength - pcbHolePitchY ) / 2 + 0 * pcbHolePitchY ) - 2.2 mm )"
equation "d826 = pcbRailThickness"
equation "d828 = pcbLeft + ( pcbWidth - pcbHolePitchX ) / 2 + 1 * pcbHolePitchX"
equation "d829 = pcbFront + ( pcbLength - pcbHolePitchY ) / 2 + 0 * pcbHolePitchY"
equation "d830 = pcbPostDiameter"
equation "d831 = pcbPostHeight"
equation "d833 = pcbLeft + ( pcbWidth - pcbHolePitchX ) / 2 + 1 * pcbHolePitchX"
equation "d834 = pcbFront + ( pcbLength - pcbHolePitchY ) / 2 + 0 * pcbHolePitchY"
equation "d835 = pcbPostPilot"
equation "d839 = ( pcbFront + ( pcbLength - pcbHolePitchY ) / 2 + 1 * pcbHolePitchY ) - 2.2 mm"
equation "d840 = ( ( 3.2 mm ) + ( 6 mm ) ) - ( 3.2 mm )"
equation "d841 = ( ( ( pcbFront + ( pcbLength - pcbHolePitchY ) / 2 + 1 * pcbHolePitchY ) - 2.2 mm ) + ( 4.4 mm ) ) - ( ( pcbFront + ( pcbLength - pcbHolePitchY ) / 2 + 1 * pcbHolePitchY ) - 2.2 mm )"
equation "d842 = pcbRailThickness"
equation "d844 = pcbLeft + ( pcbWidth - pcbHolePitchX ) / 2 + 0 * pcbHolePitchX"
equation "d845 = pcbFront + ( pcbLength - pcbHolePitchY ) / 2 + 1 * pcbHolePitchY"
equation "d846 = pcbPostDiameter"
equation "d847 = pcbPostHeight"
equation "d849 = pcbLeft + ( pcbWidth - pcbHolePitchX ) / 2 + 0 * pcbHolePitchX"
equation "d850 = pcbFront + ( pcbLength - pcbHolePitchY ) / 2 + 1 * pcbHolePitchY"
equation "d851 = pcbPostPilot"
equation "d854 = caseWidth - 9.2 mm"
equation "d855 = ( pcbFront + ( pcbLength - pcbHolePitchY ) / 2 + 1 * pcbHolePitchY ) - 2.2 mm"
equation "d856 = ( ( caseWidth - 9.2 mm ) + ( 6 mm ) ) - ( caseWidth - 9.2 mm )"
equation "d857 = ( ( ( pcbFront + ( pcbLength - pcbHolePitchY ) / 2 + 1 * pcbHolePitchY ) - 2.2 mm ) + ( 4.4 mm ) ) - ( ( pcbFront + ( pcbLength - pcbHolePitchY ) / 2 + 1 * pcbHolePitchY ) - 2.2 mm )"